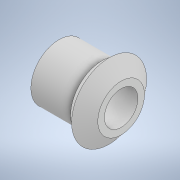
# Autodesk Inventor part: 12T
Saved by Autodesk Inventor 2021 (Build 250183000, 183)
## iProperties
Created: 2026-03-24
Part Number: 12T
Material: Genérico
Document SubType Name: Modeling
Designer: thepr
Density: 1 g/cm^3
Appearance: Valor por defecto
Author: thepr
Autodesk Inventor part; units mm, degrees
ref_plane "YZ Plane" through (0, 0, 0) normal (1, 0, 0) x (0, 1, 0)
ref_plane "XZ Plane" through (0, 0, 0) normal (0, 1, 0) x (-1, 0, 0)
ref_plane "XY Plane" through (0, 0, 0) normal (0, 0, 1) x (1, 0, 0)
sketch "Boceto1" plane through (0, 0, 0) normal (0, 0, 1) x (1, 0, 0)
  line L0 (-4.4869, 0) -> (3.3311, 0) construction
  line L1 (0, 1.5) -> (0, 2.5)
  line L2 (0, 2.5) -> (0.5, 2.5)
  line L3 (2.2, 1.5) -> (0, 1.5)
  line L4 (0, -0.67) -> (0, 4.02) projected
  line L5 (0.5, 2.5) -> (0.5, 2.8188)
  line L6 (2.2143, 1.4494) -> (2.2, 1.447)
  line L7 (2.2, 1.447) -> (2.2, 1.5)
  line L8 (0.5, 2.8188) -> (1.1223, 3.35)
  line L9 (1.1223, 3.35) -> (2.2, 2.0874)
  line L10 (2.2, 2.0874) -> (2.2, 1.447)
  line L11 (0, 1.5) -> (-3.37, 1.5)
  line L12 (-3.37, 1.5) -> (-3.37, 2.5)
  line L13 (-3.37, 2.5) -> (0, 2.5)
  point P0 (0, 0)
  point P1 (0, 2)
  dimension "d0" = 3
  dimension "d1" = 5
  dimension "d19" = 2.2
  dimension "d20" = 1.7
  dimension "d21" = 1.66
  dimension "d22" = 6.7
  dimension "d27" = 5.6377
  dimension "d31" = 5.57
  constraints: 24 end point, 5 perpendicular, 3 vertical, 1 collinear, 1 horizontal, 1 midpoint, 1 parallel, 1 point on line
  measures "d0" diameter of L3 L0
  measures "d1" diameter of L2 L0
  measures "d19" distance from line of point (0, 2) L7
  measures "d20" horizontal distance of L9.end L5.end
  measures "d21" distance of L8.end L9.end
  measures "d22" diameter of L8.end L0
  measures "d27" diameter of L5.end L0
  measures "d31" distance between parallel lines of L10 L12
revolve "Revolución1" add sketch "Boceto1" angle 360 about axis through (-10, 0, 0) along (1, 0, 0)
sketch "Boceto2" plane through (0, 0, 0) normal (0, 0, 1) x (1, 0, 0)
  circle A0 centre (-1.56, 0) radius 1.5
  line L0 (0, -2.5) -> (0, 2.5) projected
  line L1 (-0.8, 0) -> (4.8, 0) projected
  line L2 (-3.37, -2.5) -> (-3.37, 2.5) projected
  point P0 (0, 0)
  dimension "d13" = 3
  dimension "d32" = 1.81
  constraints: 1 centre point, 1 point on line
  measures "d13" diameter of A0
  measures "d32" distance from line of L2 A0.centre
extrude "Extrusión1" cut sketch "Boceto2" against normal blind 10
